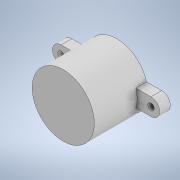
# Autodesk Inventor part: sharp_rotire_baza
Saved by Autodesk Inventor 2020 (Build 240168000, 168)
## iProperties
Created: 2023-10-29
Part Number: sharp_rotire_baza
Material: Generic
Document SubType Name: Modeling
Designer: user
Density: 1 g/cm^3
Appearance: Default
Author: user
Autodesk Inventor part; units mm, degrees
ref_plane "YZ Plane" through (0, 0, 0) normal (1, 0, 0) x (0, 1, 0)
ref_plane "XZ Plane" through (0, 0, 0) normal (0, 1, 0) x (-1, 0, 0)
ref_plane "XY Plane" through (0, 0, 0) normal (0, 0, 1) x (1, 0, 0)
sketch "Sketch1" plane through (0, 0, 0) normal (0, 0, 1) x (1, 0, 0)
  circle A0 centre (0, 0) radius 7.25
  dimension "d0" = 14.5
  constraints: 1 centre point, 1 coincident
  measures "d0" diameter of A0
extrude "Extrusion1" add sketch "Sketch1" along normal blind 10
sketch "Sketch2" plane through (0, 0, 0) normal (0, 0, -1) x (-1, 0, 0)
  line L0 (0, 0) -> (35.2836, 0) construction
  line L1 (35.2836, 0) -> (-43.1802, 0) construction
  circle A0 centre (10.5, 0) radius 2
  circle A1 centre (-10.5, 0) radius 2
  line L2 (10.5, 2) -> (6.9687, 2)
  line L3 (-10.5, 2) -> (-6.9687, 2)
  circle A2 centre (0, 0) radius 7.25 projected
  line L4 (-10.5, -2) -> (-6.9687, -2)
  circle A3 centre (10.5, 0) radius 0.75
  circle A4 centre (-10.5, 0) radius 0.75
  circle A5 centre (0, 0) radius 7.25
  line L5 (10.5, -2) -> (6.9687, -2)
  point P0 (6.9687, 2)
  dimension "d3" = 10.5
  dimension "d4" = 10.5
  dimension "d5" = 4
  dimension "d6" = 4
  dimension "d9" = 1.5
  dimension "d10" = 1.5
  constraints: 12 end point, 8 point on circle, 5 centre point, 5 coincident, 4 horizontal, 3 point on line, 1 concentric, 1 parallel, 1 tangent
  measures "d3" distance of L0.start point (10.5, 0)
  measures "d4" distance of L0.start point (-10.5, 0)
  measures "d5" diameter of A0
  measures "d6" diameter of A1
  measures "d9" diameter of A3
  measures "d10" diameter of A4
extrude "Extrusion2" add sketch "Sketch2" along normal blind 2.5
equation "\"d4\" = d3"
body "Solid1"
